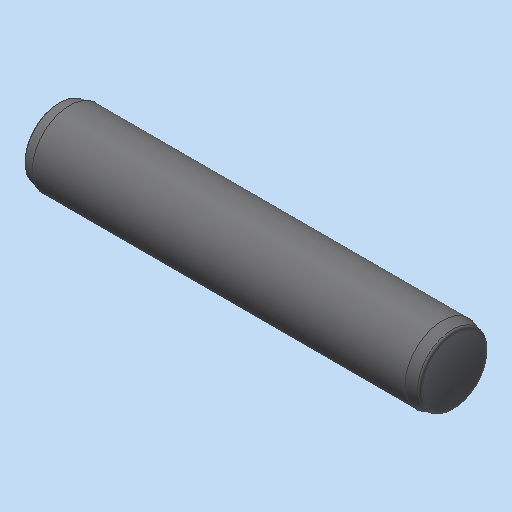
# Autodesk Inventor part: Zylinderstift_DIN_EN_ISO_8734___3x16
Saved by Autodesk Inventor 2023.3 (Build 273359000, 359)
## iProperties
Shininess: 64.0
Length Units: 11269
Angle Units: 11279
Time Units: 11290
Mass Units: 11283
Length Display Precision: 3
Angle Display Precision: 2
Compacted: True
Part Number: Zylinderstift_DIN_EN_ISO_8734___3x16
Document SubType Name: Modeling
Created: 2004-04-23
Description: =<RBPARTNOTITLE2>
Vendor: NORM8
Designer: C.Fischer
Manufacturer: Standard
Standards Organization: Custom
Density: 7.85 g/cm^3
Material: xStahl_AnP_Dummymaterial
Mass: 0.87344 g
Surface Area: 1.61894 cm^2
Volume: 0.111266 cm^3
Appearance: Stahl - normal AnP
DOC_ID: 5 F45 Zylinderstift_DIN_EN_ISO_8734___3x16
GAIN_REFID: 20__Zylinderstift_DIN_EN_ISO_8734___3x16:81C07
Control State: 0
Master: False
Checked Out: False
CNS_NB: Zylinderstift DIN EN ISO 8734 - 3x16
CNS_NN: DIN EN ISO 8734
CNS_NT: Zylinderstifte, aus gehaertetem Stahl und martensitischem nichtrostendem Stahl
CNS_NBSYN: Zylinderstift DIN EN ISO 8734 - $NENN.
CNS_LINA: Zylinderstift DIN EN ISO 8734 - 3x16
CNS_D: 3.000
CNS_L: 16.000
CNS_A: 0.500
CNS_NENN: 3x16
CNS_KT: DUMMY
PSOL_IDENT_0: {C:\partsolutions\data\23d-libs\bosch_bamberg\stifte\scherstifte\din_en_iso_8734.prj},164 {VTYP=3D},
PSOL_IDENT_1: {NB=Zylinderstift DIN EN ISO 8734 - 3x16},{NN=DIN EN ISO 8734},{DATE=26.11.2003},{GEOMDATE=26.11.200
PSOL_IDENT_2: 3},{VERSION=v1},{LINEID=380},{LINESUBID=-1},{WBVAR=}  {NB=Zylinderstift DIN EN ISO 8734 - 3x16},{LIN
PSOL_IDENT_3: A=Zylinderstift DIN EN ISO 8734 - 3x16},{KT=DUMMY},{IDNR=},{D=3.000},{L=16.000},{A=0.500},{NENN=3x16
PSOL_IDENT_4: }
DEF_STKID: T20881
Bezeichnung1: Zylinderstift DIN EN ISO 8734 - 3x16
Bezeichnung2: Zylinderstifte, aus gehaertetem Stahl u
RBPARTNOTITLE1: Parallel pins of hardened and martensitic stainless steel
RBPARTNOTITLE2: Zylinderstifte, aus gehaertetem Stahl und martensitischem nichtrostendem Stahl
RBDRAWINGMISSINGSPEC: --
AnP_Kategorie: 4
RBPARTMADEOF: ISO 8734 - 3x16 - A - St
Density: 0.0
Volumn: 0.0
Area: 0.0
PropertySet Name: Model Information
Title: Zylinderstift DIN EN ISO 8734 - 3x16
Author: C.Fischer
Keywords: =<RBPARTMADEOF>
Comments: =<RBSURFACE2>
Revision Number: 01
Autodesk Inventor part; units mm, degrees
sketch "Sketch_1" plane through (0, 0, 0) normal (0, 0, 1) x (1, 0, 0)
  line L0 (16, 0) -> (0, 0)
  arc A0 (0.2, 0) -> (0.0279, 1.2692) centre (-4.5651, 0) ccw
  arc A1 (0.0984, 1.3924) -> (0.0279, 1.2692) centre (0.1243, 1.2958) ccw
  line L1 (0.0984, 1.3924) -> (0.5, 1.5)
  line L2 (0.5, 1.5) -> (15.5, 1.5)
  line L3 (15.5, 1.5) -> (15.9016, 1.3924)
  arc A2 (15.9721, 1.2692) -> (15.9016, 1.3924) centre (15.8757, 1.2958) ccw
  arc A3 (15.9721, 1.2692) -> (15.8, 0) centre (20.5651, 0) ccw
  line L4 (15.8, 0) -> (0.2, 0)
  constraints: 10 end point, 8 point on circle, 4 centre point
revolve "Revolution1" add sketch "Sketch_1" angle 360 about axis through (16, 0, 0) along (1, 0, 0)
ref_plane "IP2_XY" through (0, 0, 0) normal (1, 0, 0) x (0, 0, -1)
ref_plane "IP2_YZ" through (0, 0, 0) normal (0, 0, -1) x (0, 1, 0)
ref_plane "IP1_XY" through (8, 0, 0) normal (1, 0, 0) x (0, 0, -1)
ref_plane "IP1_YZ" through (8, 0, 0) normal (0, 0, -1) x (0, 1, 0)
ref_plane "IP3_XY" through (16, 0, 0) normal (1, 0, 0) x (0, 0, -1)
ref_plane "IP3_YZ" through (16, 0, 0) normal (0, 0, -1) x (0, 1, 0)
